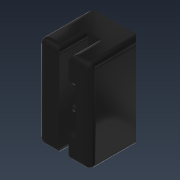
# Autodesk Inventor part: SP52V1 Plastico Roldana
Saved by Autodesk Inventor 2021.2 (Build 252289000, 289)
## iProperties
Created: 2026-09-01
Part Number: SP52V1 Plastico Roldana
Material: ABS Plastic
Document SubType Name: Modeling
Designer: nelso
Density: 1.06 g/cm^3
Appearance: Smooth - Black
Author: nelso
Autodesk Inventor part; units mm, degrees
sketch "Sketch1" plane through (0, 0, 0) normal (0, 1, 0) x (-1, 0, 0)
  line L0 (-22.5, 40) -> (22.5, 40)
  line L1 (22.5, 40) -> (22.5, -40)
  line L2 (22.5, -40) -> (-22.5, -40)
  line L3 (-22.5, -40) -> (-22.5, 40)
  line L4 (-22.5, 40) -> (22.5, -40) construction
  line L5 (22.5, 40) -> (-22.5, -40) construction
  point P0 (0, 0)
  dimension "d0" = 45
  dimension "d1" = 80
  constraints: 12 end point, 2 midpoint, 2 parallel, 1 horizontal, 1 perpendicular
  measures "d0" distance of L1.end L2.end
  measures "d1" distance of L0.end L1.end
extrude "Extrusion1" add sketch "Sketch1" along normal mid plane 45
sketch "Sketch2" plane through (0, -22.5, 0) normal (0, -1, 0) x (1, 0, 0)
  line L0 (22.5, -40) -> (-22.5, -40) projected
  line L1 (4, 40) -> (-4, 40)
  line L2 (-4, 40) -> (-4, -40)
  line L3 (-4, -40) -> (4, -40)
  line L4 (4, -40) -> (4, 40)
  line L5 (4, 40) -> (-4, -40) construction
  line L6 (-4, 40) -> (4, -40) construction
  point P0 (0, 0)
  dimension "d4" = 8
  constraints: 12 end point, 2 midpoint, 2 parallel, 1 horizontal, 1 perpendicular, 1 point on line
  measures "d4" distance of L3.end L2.end
extrude "Extrusion2" cut sketch "Sketch2" against normal blind 25
chamfer "Chamfer1" distance 5 angle 45 2 edges at (22.5, 22.5, 0) (-22.5, 22.5, 0)
chamfer "Chamfer2" distance 0.3 angle 45 2 edges at (0, 22.5, 40) (0, 22.5, -40)
fillet "Fillet1" radius 5 14 edges at (22.5, -2.5, 40) (-22.5, -2.5, 40) (22.5, -2.5, -40) (-22.5, -2.5, -40) (4, -10, -40) (-4, -10, -40) (-4, -10, 40) (4, -10, 40) (-22.5, -22.5, 0) (-13.25, -22.5, 40) (-13.25, -22.5, -40) (13.25, -22.5, -40) (22.5, -22.5, 0) (13.25, -22.5, 40)
sketch "Sketch5" plane through (4, -22.5, -35) normal (-1, 0, 0) x (0, 0, 1)
  line L0 (70, 0) -> (0, 0) projected
  line L1 (35, 0) -> (14.5, 0)
  line L2 (70, 25) -> (0, 25) projected
  line L3 (14.5, 0) -> (14.5, 25)
  line L4 (14.5, 25) -> (55.5, 25)
  line L5 (55.5, 25) -> (55.5, 0)
  line L6 (55.5, 0) -> (14.5, 0)
  point P0 (55.5, 0)
  point P1 (55.5, 25)
  dimension "d31" = 20.5
  dimension "d32" = 41
  constraints: 10 end point, 2 parallel, 2 point on line, 1 midpoint, 1 perpendicular, 1 vertical
  measures "d31" distance of L1.start L1.end
  measures "d32" distance of L3.end L4.end
extrude "Extrusion4" cut sketch "Sketch5" against normal blind 6
ref_plane "Work Plane1" through (13.25, -22.5, 35) normal (-1, 0, 0) x (0, 0, 1)
sketch "Sketch9" plane through (-22.5, -17.5, -35) normal (-1, 0, 0) x (0, 0, 1)
  circle A0 centre (25, 10) radius 4
  circle A1 centre (45, 10) radius 4
  point P0 (35, 17.5)
  dimension "d54" = 8
  dimension "d55" = 8
  constraints: 2 centre point
  measures "d54" diameter of A0
  measures "d55" diameter of A1
ref_plane "Work Plane2" through (-2, -22.5, -35) normal (1, 0, 0) x (0, 1, 0)
extrude "Extrusion7" cut sketch "Sketch9" against normal up to surface (20.5 mm away)
ref_plane "Work Plane3" through (13.25, -17.5, 35) normal (1, 0, 0) x (0, 0, -1)
sketch "Sketch11" plane through (13.25, -17.5, 35) normal (1, 0, 0) x (0, 0, -1)
  circle A0 centre (25, 10) radius 2.0586 projected
  circle A1 centre (45, 10) radius 2.0586 projected
  line L0 (45, 5.8431) -> (41.4, 7.9215)
  line L1 (41.4, 7.9215) -> (41.4, 12.0785)
  line L2 (48.6, 12.0785) -> (48.6, 7.9215)
  line L3 (48.6, 7.9215) -> (45, 5.8431)
  line L4 (25, 5.8431) -> (21.4, 7.9215)
  line L5 (21.4, 7.9215) -> (21.4, 12.0785)
  line L6 (28.6, 12.0785) -> (28.6, 7.9215)
  line L7 (28.6, 7.9215) -> (25, 5.8431)
  line L8 (48.6, 14.1569) -> (41.4, 14.1569)
  line L9 (41.4, 14.1569) -> (41.4, 12.0785)
  line L10 (48.6, 12.0785) -> (48.6, 14.1569)
  line L11 (28.6, 14.1569) -> (21.4, 14.1569)
  line L12 (21.4, 14.1569) -> (21.4, 12.0785)
  line L13 (28.6, 12.0785) -> (28.6, 14.1569)
  point P0 (35, 17.5)
  dimension "d58" = 7.2
  dimension "d59" = 7.2
  constraints: 28 end point, 2 coincident, 2 horizontal, 2 parallel, 2 perpendicular, 2 point on line, 16 other
  measures "d58" distance between parallel lines of L2 L1
  measures "d59" distance between parallel lines of L5 L6
extrude "Extrusion8" cut sketch "Sketch11" along normal blind 3.4
sketch "Sketch12" plane through (4, -22.5, 35) normal (-1, 0, 0) x (0, 0, 1)
  circle A0 centre (-45, 15) radius 2.0586 projected
  circle A1 centre (-25, 15) radius 2.25 projected
  point P0 (-35, 22.5)
  constraints: 2 coincident
hole "Hole3" at (4, -7.5, -10) at (4, -7.5, 10) direction (1, 0, 0) diameter 4.5 depth 15 clearance for "Countersunk Flat Head Screw ISO 2009/7046" size "M4" standard "ISO"
equation "\"d59\" = d58"
body "Solid1"
